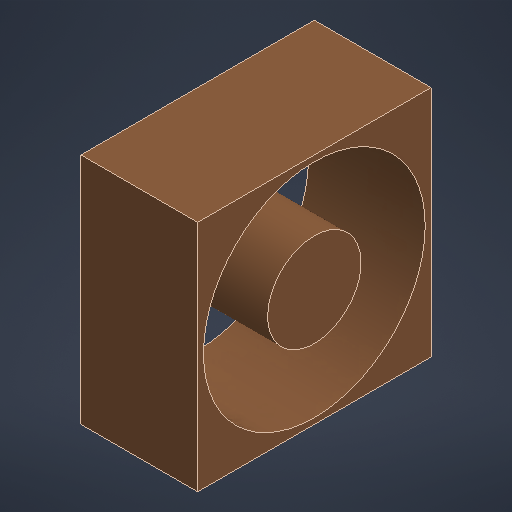
# Autodesk Inventor part: ref_fan
Saved by Autodesk Inventor 2027.1 (Build 311270010, 270A)
## iProperties
Created: 2026-10-22
Part Number: ref_fan
Material: 일반
Document SubType Name: Modeling
Designer: sungjun
Density: 1 g/cm^3
Appearance: ref_fan_c
Author: sungjun
Autodesk Inventor part; units mm, degrees
ref_plane "작업 평면1" through (0, 0, 23) normal (0, 0, 1) x (1, 0, 0)
sketch "스케치1" plane through (0, 0, 23) normal (0, 0, 1) x (1, 0, 0)
  line L0 (3, 34.5) -> (23, 34.5)
  line L1 (23, 34.5) -> (23, 74.5)
  line L2 (23, 74.5) -> (3, 74.5)
  line L3 (3, 74.5) -> (3, 34.5)
  constraints: 8 end point, 2 parallel, 1 horizontal, 1 perpendicular
extrude "돌출1" add sketch "스케치1" along normal mid plane 40
ref_plane "작업 평면2" through (13, 0, 0) normal (1, 0, 0) x (0, 1, 0)
sketch "스케치2" plane through (13, 0, 0) normal (1, 0, 0) x (0, 1, 0)
  circle A0 centre (54.5, 23) radius 19
  constraints: 1 centre point
extrude "돌출2" cut sketch "스케치2" along normal mid plane 22
ref_plane "작업 평면3" through (13, 0, 0) normal (1, 0, 0) x (0, 1, 0)
sketch "스케치3" plane through (13, 0, 0) normal (1, 0, 0) x (0, 1, 0)
  circle A0 centre (54.5, 23) radius 8
  constraints: 1 centre point
extrude "돌출3" add sketch "스케치3" along normal mid plane 20
